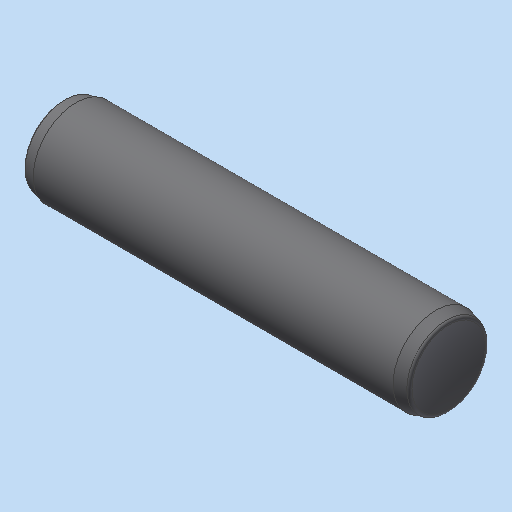
# Autodesk Inventor part: Zylinderstift_DIN_EN_ISO_8734___4x18
Saved by Autodesk Inventor 2023.3 (Build 273359000, 359)
## iProperties
Shininess: 64.0
Length Units: 11269
Angle Units: 11279
Time Units: 11290
Mass Units: 11283
Length Display Precision: 3
Angle Display Precision: 2
Compacted: True
Part Number: Zylinderstift_DIN_EN_ISO_8734___4x18
Document SubType Name: Modeling
Created: 2004-04-23
Description: =<RBPARTNOTITLE2>
Vendor: NORM8
Designer: C.Fischer
Manufacturer: Standard
Standards Organization: Custom
Material: xStahl_AnP_Dummymaterial
Density: 7.85 g/cm^3
Appearance: Stahl - normal AnP
Mass: 1.74385 g
Surface Area: 2.46268 cm^2
Volume: 0.222147 cm^3
Density: 0.0
Volumn: 0.0
Area: 0.0
PropertySet Name: Model Information
Control State: 0
Master: False
Checked Out: False
CNS_NB: Zylinderstift DIN EN ISO 8734 - 4x18
CNS_NN: DIN EN ISO 8734
CNS_NT: Zylinderstifte, aus gehaertetem Stahl und martensitischem nichtrostendem Stahl
CNS_NBSYN: Zylinderstift DIN EN ISO 8734 - $NENN.
CNS_LINA: Zylinderstift DIN EN ISO 8734 - 4x18
CNS_D: 4.000
CNS_L: 18.000
CNS_A: 0.630
CNS_NENN: 4x18
CNS_KT: DUMMY
PSOL_IDENT_0: {C:\partsolutions\data\23d-libs\bosch_bamberg\stifte\scherstifte\din_en_iso_8734.prj},164 {VTYP=3D},
PSOL_IDENT_1: {NB=Zylinderstift DIN EN ISO 8734 - 4x18},{NN=DIN EN ISO 8734},{DATE=26.11.2003},{GEOMDATE=26.11.200
PSOL_IDENT_2: 3},{VERSION=v1},{LINEID=500},{LINESUBID=-1},{WBVAR=}  {NB=Zylinderstift DIN EN ISO 8734 - 4x18},{LIN
PSOL_IDENT_3: A=Zylinderstift DIN EN ISO 8734 - 4x18},{KT=DUMMY},{IDNR=},{D=4.000},{L=18.000},{A=0.630},{NENN=4x18
PSOL_IDENT_4: }
RBPARTNOTITLE1: Parallel pins of hardened and martensitic stainless steel
RBPARTNOTITLE2: Zylinderstifte, aus gehaertetem Stahl und martensitischem nichtrostendem Stahl
RBDRAWINGMISSINGSPEC: --
AnP_Kategorie: 4
RBPARTMADEOF: ISO 8734 - 4x18 - A - St
Title: Zylinderstift DIN EN ISO 8734 - 4x18
Author: C.Fischer
Keywords: =<RBPARTMADEOF>
Comments: =<RBSURFACE2>
Revision Number: 01
Autodesk Inventor part; units mm, degrees
sketch "Sketch_1" plane through (0, 0, 0) normal (0, 0, 1) x (1, 0, 0)
  line L0 (18, 0) -> (0, 0)
  arc A0 (0.252, 0) -> (0.0327, 1.7104) centre (-6.5273, 0) ccw
  arc A1 (0.122, 1.8639) -> (0.0327, 1.7104) centre (0.1546, 1.7422) ccw
  line L1 (0.122, 1.8639) -> (0.63, 2)
  line L2 (0.63, 2) -> (17.37, 2)
  line L3 (17.37, 2) -> (17.878, 1.8639)
  arc A2 (17.9673, 1.7104) -> (17.878, 1.8639) centre (17.8454, 1.7422) ccw
  arc A3 (17.9673, 1.7104) -> (17.748, 0) centre (24.5273, 0) ccw
  line L4 (17.748, 0) -> (0.252, 0)
  constraints: 10 end point, 8 point on circle, 4 centre point
revolve "Revolution1" add sketch "Sketch_1" angle 360 about axis through (18, 0, 0) along (1, 0, 0)
ref_plane "IP2_XY" through (0, 0, 0) normal (1, 0, 0) x (0, 0, -1)
ref_plane "IP2_YZ" through (0, 0, 0) normal (0, 0, -1) x (0, 1, 0)
ref_plane "IP1_XY" through (9, 0, 0) normal (1, 0, 0) x (0, 0, -1)
ref_plane "IP1_YZ" through (9, 0, 0) normal (0, 0, -1) x (0, 1, 0)
ref_plane "IP3_XY" through (18, 0, 0) normal (1, 0, 0) x (0, 0, -1)
ref_plane "IP3_YZ" through (18, 0, 0) normal (0, 0, -1) x (0, 1, 0)
